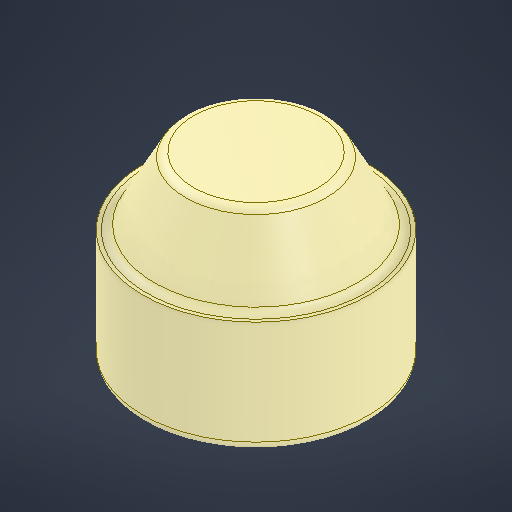
# Autodesk Inventor part: Product Base
Saved by Autodesk Inventor 2027.1 (Build 311270010, 270A)
## iProperties
Created: 2026-10-02
Part Number: Product Base
Material: Nylon 6/6
Document SubType Name: Modeling
Designer: Ahmed
Density: 1.13 g/cm^3
Appearance: Nylon 6
Mass: 32.5243 g
Surface Area: 121.529 cm^2
Volume: 28.7826 cm^3
Author: Ahmed
Autodesk Inventor part; units mm, degrees
ref_plane "YZ Plane" through (0, 0, 0) normal (1, 0, 0) x (0, 1, 0)
ref_plane "XZ Plane" through (0, 0, 0) normal (0, 1, 0) x (-1, 0, 0)
ref_plane "XY Plane" through (0, 0, 0) normal (0, 0, 1) x (1, 0, 0)
sketch "Sketch2" plane through (0, 0, 0) normal (0, 0, 1) x (1, 0, 0)
  line L0 (0, 0) -> (25, 0)
  line L1 (25, 0) -> (25, 25)
  line L2 (0, 0) -> (0, 40)
  line L3 (0, 40) -> (15, 40)
  line L4 (0, -8) -> (0, 48) projected
  line L5 (25, 25) -> (23, 25)
  line L6 (23, 25) -> (15, 40)
  line L7 (12, 35) -> (5, 35)
  line L8 (5, 35) -> (5, 5)
  line L9 (5, 5) -> (20, 5)
  line L10 (20, 5) -> (20, 20)
  line L11 (20, 20) -> (20, 20)
  line L12 (20, 20) -> (12, 35)
  line L13 (5, 5) -> (5, 0)
  line L14 (20, 5) -> (20, 0)
  line L15 (5, 35) -> (0, 35)
  point P0 (20, 20)
  dimension "d7" = 25
  dimension "d8" = 25
  dimension "d9" = 40
  dimension "d10" = 15
  dimension "d13" = 2
  dimension "d16" = 5
  constraints: 30 end point, 4 perpendicular, 3 horizontal, 3 point on line, 1 parallel, 1 vertical, 5 other
  measures "d7" distance of L0.start L0.end
  measures "d8" distance of L0.end L1.end
  measures "d9" distance of L0.start L2.end
  measures "d10" distance of L2.end L3.end
  measures "d13" distance of L1.end L5.end
  measures "d16" distance between parallel lines of L6 L12
revolve "Revolution1" add sketch "Sketch2" angle 360 about axis through (0, -10, 0) along (0, 1, 0) contours L2 L3 L6 L5 L1 L0 L14 L10 L12 L7 L15
fillet "Fillet3" radius 2 3 edges at (-15, 40, 0) (-25, 0, 0) (-23, 25, 0)
body "Solid1"
